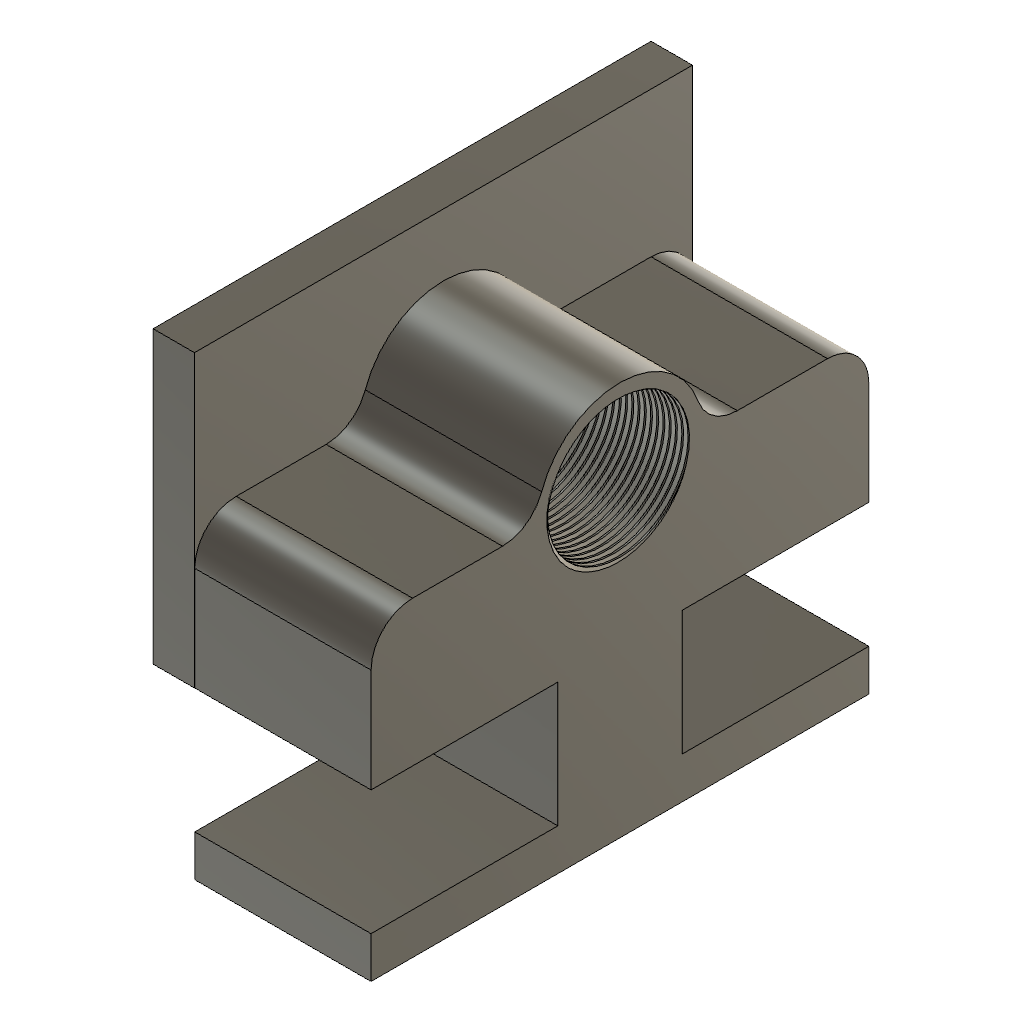
body+3 (Autodesk Fusion 360 design; units mm, degrees)
part number: 2026-10-03-21-04-10-954
part number: 2026-10-07-15-16-42-855
Autodesk Fusion 360 part; units mm, degrees
sketch "Sketch1" plane through (0, 0, 0) normal (1, 0, 0) x (0, 1, 0)
  circle A0 centre (0.0527, 74.7178) radius 20
  line L0 (15.0529, 9.7178) -> (60.0529, 9.718)
  line L1 (60.0529, 9.718) -> (60.0529, -0.282)
  circle A1 centre (0.0527, 74.7178) radius 15
  line L2 (15.0529, 9.7178) -> (15.0528, 39.7178)
  line L3 (0.0722, -19.5213) -> (0.0718, 100.4787)
  line L4 (15.0528, 39.7178) -> (60.0528, 39.718)
  line L5 (60.0528, 39.718) -> (60.0527, 64.718)
  line L6 (50.0527, 74.7179) -> (0.0527, 74.7178)
  line L7 (60.0529, -0.282) -> (0.0529, -0.2822)
  line L8 (-14.9088, 39.7177) -> (-59.9088, 39.7176)
  line L9 (-59.9087, -0.2824) -> (0.0913, -0.2822)
  line L10 (-14.9087, 9.7177) -> (-59.9087, 9.7176)
  line L11 (-14.9087, 9.7177) -> (-14.9088, 39.7177)
  line L12 (-59.9088, 39.7176) -> (-59.9089, 64.7176)
  line L13 (-59.9087, 9.7176) -> (-59.9087, -0.2824)
  line L14 (-49.9089, 74.7176) -> (0.0911, 74.7178)
  arc A2 (60.0527, 64.718) -> (50.0527, 74.7179) centre (50.0527, 64.7179) ccw
  arc A3 (-49.9089, 74.7176) -> (-59.9089, 64.7176) centre (-49.9089, 64.7176) ccw
  point P0 (0.0722, -19.5213)
  point P1 (60.0527, 74.718)
  dimension "d3" = 40
  dimension "d41" = 10
  dimension "d44" = -5
  dimension "d77" = 45
  dimension "d81" = 30
  dimension "d83" = 120
  dimension "d84" = 45
  dimension "d85" = 35
  dimension "d86" = 60
  dimension "d87" = 60
  dimension "d88" = 10
  constraint perpendicular L0 L1
  constraint perpendicular L0 L2
  constraint coincident P0 L3.start
  constraint perpendicular L2 L4
  constraint perpendicular L4 L5
  constraint perpendicular L3 L6
  constraint perpendicular L3 L7
  constraint symmetric L0.start L3 L10.start
  constraint symmetric L0.end L3 L10.end
  constraint symmetric L1.end L3 L9.start
  constraint symmetric L2.end L3 L8.start
  constraint symmetric L3 L4.end L8.end
  constraint symmetric L3 A0.centre L14.end
  constraint symmetric L3 L7.end L9.end
  constraint coincident A0.centre A1.centre
  constraint coincident P1 L5
  constraint coincident P1 L6
  constraint tangent L5 A2
  constraint tangent L6 A2
  constraint tangent L12 A3
  constraint tangent L14 A3
  constraint equal A2 A3
  measures "d3" diameter of A0
  measures "d41" distance of L0.end L1.end
  measures "d77" horizontal distance of L0.start L0.end
  measures "d81" distance of L0.start L2.end
  measures "d83" distance of P0 L3.end
  measures "d84" distance of L2.end L4.end
  measures "d85" distance of L4.end P1
  measures "d86" distance of P1 A0.centre
  measures "d87" distance of L1.end L7.end
  measures "d88" radius of A2
extrude "Extrude6" add sketch "Sketch1" along normal blind 42.5 contours A0 A1 L3 L6 | A0 L0 L1 L2 L3 L4 L5 L6 L7 L9 A2 | A0 A1 L3 L6 | A0 A1 L3 L14 | A0 L3 L7 L8 L9 L10 L11 L12 L13 L14 A3 | A0 A1 L3 L14 makes body 1
fillet "Fillet9" radius 10 1 edges at (21.25, -19.9473, 74.7177) on bodies 1
fillet "Fillet10" radius 10 1 edges at (21.25, 20.0527, 74.7178) on bodies 1
thread "Thread1" "ISO Metric profile 35.0 M35x1.5 M35x1.5 6H" major diameter 35.208 minor diameter 33.526 pitch 1.5 angle 60 modelled right hand crest width 0.4036 on face at (14.1667, 14.9781, 73.2243) crest through (0.375, 16.8157, 74.7178) on bodies 1
sketch "Sketch3" plane through (0, 0, 0) normal (-1, 0, 0) x (0, -1, 0)
  spline S0 degree 3 poles (4.5145, 91.719) (6.7034, 91.0755) (8.7462, 90.0126) (12.2908, 87.1733) (13.7634, 85.4306) (15.9445, 81.4948) (16.6387, 79.3436) (17.1573, 74.9162) (16.9846, 72.6836) (16.0241, 69.2506) (15.508, 68.0015) (14.1935, 65.6598) (13.4014, 64.5745) (12.4887, 63.5951) knots 0 0 0 0 0.684446 0.684446 1.362736 1.362736 2.03487 2.03487 2.700845 2.700845 3.105174 3.105174 3.507164 3.507164 3.507164 3.507164
  arc A0 (-12.594, 63.5951) -> (12.4887, 63.5951) centre (-0.0527, 74.7178) ccw
  spline S1 degree 3 poles (-12.594, 63.5951) (-14.0887, 65.199) (-15.2543, 67.0806) (-16.8096, 71.2032) (-17.1771, 73.4073) (-17.0496, 77.8537) (-16.5481, 80.0529) (-14.7251, 84.1563) (-13.4141, 86.0178) (-10.7797, 88.5382) (-9.6638, 89.3754) (-7.2506, 90.772) (-5.9611, 91.3247) (-4.6198, 91.719) knots 0 0 0 0 0.65773 0.65773 1.321613 1.321613 1.991648 1.991648 2.667834 2.667834 3.084534 3.084534 3.503568 3.503568 3.503568 3.503568
  arc A1 (4.5145, 91.719) -> (-4.6198, 91.719) centre (-0.0527, 74.7178) ccw
  line L0 (-15.0528, 39.7178) -> (-15.0529, 9.7178)
  line L1 (-15.0529, 9.7178) -> (-60.0529, 9.718)
  line L2 (-60.0529, 9.718) -> (-60.0529, -0.282)
  line L3 (-60.0529, -0.282) -> (59.9087, -0.2824)
  line L4 (59.9087, -0.2824) -> (59.9087, 9.7176)
  line L5 (59.9087, 9.7176) -> (14.9087, 9.7177)
  line L6 (14.9087, 9.7177) -> (14.9088, 39.7177)
  line L7 (14.9088, 39.7177) -> (59.9088, 39.7176)
  line L8 (59.9088, 39.7176) -> (59.9089, 64.7176)
  arc A2 (59.9089, 64.7176) -> (49.9089, 74.7176) centre (49.9089, 64.7176) ccw
  line L9 (49.9089, 74.7176) -> (28.2316, 74.7177)
  arc A3 (18.8035, 81.3844) -> (28.2316, 74.7177) centre (28.2317, 84.7177) ccw
  arc A4 (18.8035, 81.3844) -> (-18.9088, 81.3845) centre (-0.0527, 74.7178) ccw
  arc A5 (-28.3369, 74.7179) -> (-18.9088, 81.3845) centre (-28.3369, 84.7179) ccw
  line L10 (-28.3369, 74.7179) -> (-50.0527, 74.7179)
  arc A6 (-50.0527, 74.7179) -> (-60.0527, 64.718) centre (-50.0527, 64.7179) ccw
  line L11 (-60.0527, 64.718) -> (-60.0528, 39.718)
  line L12 (-60.0528, 39.718) -> (-15.0528, 39.7178)
  line L13 (-60.0527, 109.7178) -> (59.9473, 109.7178)
  line L14 (59.9473, 109.7178) -> (59.9473, 39.7178)
  line L15 (59.9473, 39.7178) -> (-60.0527, 39.7178)
  line L16 (-60.0527, 39.7178) -> (-60.0527, 109.7178)
  line L17 (-60.0527, 109.7178) -> (59.9473, 39.7178) construction
  line L18 (59.9473, 109.7178) -> (-60.0527, 39.7178) construction
  point P0 (-0.0527, 74.7178)
  dimension "d97" = 120
  dimension "d98" = 70
  constraint horizontal L13
  constraint perpendicular L13 L14
  constraint parallel L13 L15
  constraint parallel L14 L16
  constraint coincident L17 P0
  constraint coincident L18 P0
  constraint coincident P0 A0.centre
  measures "d97" distance of L14.end L15.end
  measures "d98" distance of L13.end L14.end
extrude "Extrude7" add sketch "Sketch3" along normal blind 10 contours S0 A0 S1 A1 | L7 L8 A2 L9 A3 A4 A5 L10 A6 L11 L12 L15 L16 | L8 A2 L9 A3 A4 A5 L10 A6 L13 L14 L15 L16 bodies 1
copy_body "Body->Comp5" bodies 1 removing the originals makes body 2 in component "Slider"
component "Slider" placed x (1, 0, 0) y (0, 1, 0) z (0, 0, 1) at (0, 0, 0)
named bodies: "Slider"
